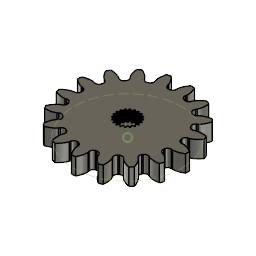
Main+assembly (Autodesk Fusion 360 archive; units mm, degrees)
design "Gear"
part number: 2025-12-15-16-50-46-728
description: Spur Gear; Module: 1.5; Num Teeth: 17; Pressure Angle: 20.0; Backlash: 0.15 mm
part number: 2025-12-15-16-51-44-285
Autodesk Fusion 360 part; units mm, degrees
(part 1 of 6)
sketch "Sketch1" plane through (0, 0, 0) normal (0, 0, 1) x (1, 0, 0) in component "Spur Gear (17 teeth)"
  circle A0 centre (0, 0) radius 10.8992
  circle A1 centre (0, 0) radius 0.5
extrude "Extrude1" add sketch "Sketch1" along normal blind 4 in component "Spur Gear (17 teeth)"
sketch "Sketch2" plane through (0, 0, 0) normal (0, 0, 1) x (1, 0, 0) in component "Spur Gear (17 teeth)"
  spline S0 degree 5 poles (11.9159, -1.2481) (11.9225, -1.2488) (11.9358, -1.25) (11.9557, -1.2512) (11.9823, -1.2518) (12.0157, -1.2511) (12.0491, -1.2494) (12.0825, -1.247) (12.116, -1.2443) (12.1495, -1.2413) (12.183, -1.238) (12.2166, -1.2344) (12.2501, -1.2304) (12.2837, -1.2259) (12.3173, -1.2209) (12.3509, -1.2154) (12.3845, -1.2095) (12.4181, -1.2032) (12.4517, -1.1966) (12.4853, -1.1898) (12.5189, -1.1827) (12.5525, -1.1752) (12.5861, -1.1675) (12.6197, -1.1594) (12.6533, -1.1511) (12.6869, -1.1424) (12.7205, -1.1334) (12.7541, -1.1241) (12.7876, -1.1146) (12.8212, -1.1048) (12.8547, -1.0948) (12.8882, -1.0845) (12.9218, -1.0739) (12.9553, -1.063) (12.9888, -1.0519) (13.0222, -1.0406) (13.0557, -1.029) (13.0891, -1.0171) (13.1225, -1.0051) (13.1559, -0.9927) (13.1893, -0.9802) (13.2227, -0.9674) (13.256, -0.9543) (13.2893, -0.9411) (13.3226, -0.9276) (13.3559, -0.9139) (13.3891, -0.8999) (13.4223, -0.8858) (13.4555, -0.8714) (13.4887, -0.8568) (13.5218, -0.842) (13.5549, -0.8269) (13.588, -0.8117) (13.6211, -0.7962) (13.6541, -0.7805) (13.6871, -0.7646) (13.72, -0.7485) (13.753, -0.7322) (13.7858, -0.7157) (13.8187, -0.699) (13.8515, -0.6821) (13.8843, -0.665) (13.9171, -0.6476) (13.9498, -0.6301) (13.9825, -0.6124) (14.0151, -0.5945) (14.0477, -0.5764) (14.0803, -0.558) (14.1128, -0.5395) (14.1453, -0.5209) (14.1777, -0.502) (14.2036, -0.4867) (14.223, -0.4752) (14.236, -0.4674) (14.2425, -0.4636) knots 0 0 0 0 0 0 0.01428571 0.02857143 0.04285714 0.05714286 0.07142857 0.08571429 0.1 0.11428571 0.12857143 0.14285714 0.15714286 0.17142857 0.18571429 0.2 0.21428571 0.22857143 0.24285714 0.25714286 0.27142857 0.28571429 0.3 0.31428571 0.32857143 0.34285714 0.35714286 0.37142857 0.38571429 0.4 0.41428571 0.42857143 0.44285714 0.45714286 0.47142857 0.48571429 0.5 0.51428571 0.52857143 0.54285714 0.55714286 0.57142857 0.58571429 0.6 0.61428571 0.62857143 0.64285714 0.65714286 0.67142857 0.68571429 0.7 0.71428571 0.72857143 0.74285714 0.75714286 0.77142857 0.78571429 0.8 0.81428571 0.82857143 0.84285714 0.85714286 0.87142857 0.88571429 0.9 0.91428571 0.92857143 0.94285714 0.95714286 0.97142857 0.98571429 1 1 1 1 1 1
  spline S1 degree 5 poles (11.9159, 1.2481) (11.9225, 1.2488) (11.9358, 1.25) (11.9557, 1.2512) (11.9823, 1.2518) (12.0157, 1.2511) (12.0491, 1.2494) (12.0825, 1.247) (12.116, 1.2443) (12.1495, 1.2413) (12.183, 1.238) (12.2166, 1.2344) (12.2501, 1.2304) (12.2837, 1.2259) (12.3173, 1.2209) (12.3509, 1.2154) (12.3845, 1.2095) (12.4181, 1.2032) (12.4517, 1.1966) (12.4853, 1.1898) (12.5189, 1.1827) (12.5525, 1.1752) (12.5861, 1.1675) (12.6197, 1.1594) (12.6533, 1.1511) (12.6869, 1.1424) (12.7205, 1.1334) (12.7541, 1.1241) (12.7876, 1.1146) (12.8212, 1.1048) (12.8547, 1.0948) (12.8882, 1.0845) (12.9218, 1.0739) (12.9553, 1.063) (12.9888, 1.0519) (13.0222, 1.0406) (13.0557, 1.029) (13.0891, 1.0171) (13.1225, 1.0051) (13.1559, 0.9927) (13.1893, 0.9802) (13.2227, 0.9674) (13.256, 0.9543) (13.2893, 0.9411) (13.3226, 0.9276) (13.3559, 0.9139) (13.3891, 0.8999) (13.4223, 0.8858) (13.4555, 0.8714) (13.4887, 0.8568) (13.5218, 0.842) (13.5549, 0.8269) (13.588, 0.8117) (13.6211, 0.7962) (13.6541, 0.7805) (13.6871, 0.7646) (13.72, 0.7485) (13.753, 0.7322) (13.7858, 0.7157) (13.8187, 0.699) (13.8515, 0.6821) (13.8843, 0.665) (13.9171, 0.6476) (13.9498, 0.6301) (13.9825, 0.6124) (14.0151, 0.5945) (14.0477, 0.5764) (14.0803, 0.558) (14.1128, 0.5395) (14.1453, 0.5209) (14.1777, 0.502) (14.2036, 0.4867) (14.223, 0.4752) (14.236, 0.4674) (14.2425, 0.4636) knots 0 0 0 0 0 0 0.01428571 0.02857143 0.04285714 0.05714286 0.07142857 0.08571429 0.1 0.11428571 0.12857143 0.14285714 0.15714286 0.17142857 0.18571429 0.2 0.21428571 0.22857143 0.24285714 0.25714286 0.27142857 0.28571429 0.3 0.31428571 0.32857143 0.34285714 0.35714286 0.37142857 0.38571429 0.4 0.41428571 0.42857143 0.44285714 0.45714286 0.47142857 0.48571429 0.5 0.51428571 0.52857143 0.54285714 0.55714286 0.57142857 0.58571429 0.6 0.61428571 0.62857143 0.64285714 0.65714286 0.67142857 0.68571429 0.7 0.71428571 0.72857143 0.74285714 0.75714286 0.77142857 0.78571429 0.8 0.81428571 0.82857143 0.84285714 0.85714286 0.87142857 0.88571429 0.9 0.91428571 0.92857143 0.94285714 0.95714286 0.97142857 0.98571429 1 1 1 1 1 1
  arc A0 (14.2425, -0.4636) -> (14.2425, 0.4636) centre (0, 0) ccw
  line L0 (10.83, -1.1354) -> (11.9159, -1.2481)
  line L1 (10.83, 1.1354) -> (11.9159, 1.2481)
  line L2 (10.83, -1.1354) -> (10.83, 1.1354)
  point P0 (12.0789, -1.2472)
  point P1 (12.2435, -1.2311)
  point P2 (12.4089, -1.2049)
  point P3 (12.575, -1.17)
  point P4 (12.7416, -1.1275)
  point P5 (12.9085, -1.078)
  point P6 (13.0757, -1.0219)
  point P7 (13.2429, -0.9594)
  point P8 (13.4101, -0.891)
  point P9 (13.5772, -0.8166)
  point P10 (13.7441, -0.7366)
  point P11 (13.9106, -0.651)
  point P12 (14.0768, -0.5599)
  point P13 (12.0789, 1.2472)
  point P14 (12.2435, 1.2311)
  point P15 (12.4089, 1.2049)
  point P16 (12.575, 1.17)
  point P17 (12.7416, 1.1275)
  point P18 (12.9085, 1.078)
  point P19 (13.0757, 1.0219)
  point P20 (13.2429, 0.9594)
  point P21 (13.4101, 0.891)
  point P22 (13.5772, 0.8166)
  point P23 (13.7441, 0.7366)
  point P24 (13.9106, 0.651)
  point P25 (14.0768, 0.5599)
extrude "Extrude2" add sketch "Sketch2" along normal blind 4 in component "Spur Gear (17 teeth)"
fillet "Fillet1" radius 0.8 2 edges at (10.8398, -1.1364, 2) (10.8398, 1.1364, 2) in component "Spur Gear (17 teeth)"
pattern_circular "C-Pattern1" count 17 over 360 about axis through (0, 0, 0) along (0, 0, 1) of "Extrude2", "Fillet1" in component "Spur Gear (17 teeth)"
sketch "Sketch3" plane through (0, 0, 0) normal (0, 0, 1) x (1, 0, 0) in component "Spur Gear (17 teeth)"
  circle A0 centre (0, 0) radius 12.75 construction
sketch "Sketch8" plane through (0, 0, 4) normal (0, 0, 1) x (-1, 0, 0)
  arc A0 (-10.6889, 2.1309) -> (-10.7368, 1.8743) centre (0, 0) ccw
  arc A1 (-11.6075, 1.2161) -> (-10.7368, 1.8743) centre (-11.5249, 2.0118) ccw
  line L0 (-11.6075, 1.2161) -> (-11.9159, 1.2481)
  spline S0 degree 5 poles (-11.9159, 1.2481) (-11.9225, 1.2488) (-11.9358, 1.25) (-11.9557, 1.2512) (-11.9823, 1.2518) (-12.0157, 1.2511) (-12.0491, 1.2494) (-12.0825, 1.247) (-12.116, 1.2443) (-12.1495, 1.2413) (-12.183, 1.238) (-12.2166, 1.2344) (-12.2501, 1.2304) (-12.2837, 1.2259) (-12.3173, 1.2209) (-12.3509, 1.2154) (-12.3845, 1.2095) (-12.4181, 1.2032) (-12.4517, 1.1966) (-12.4853, 1.1898) (-12.5189, 1.1827) (-12.5525, 1.1752) (-12.5861, 1.1675) (-12.6197, 1.1594) (-12.6533, 1.1511) (-12.6869, 1.1424) (-12.7205, 1.1334) (-12.7541, 1.1241) (-12.7876, 1.1146) (-12.8212, 1.1048) (-12.8547, 1.0948) (-12.8882, 1.0845) (-12.9218, 1.0739) (-12.9553, 1.063) (-12.9888, 1.0519) (-13.0222, 1.0406) (-13.0557, 1.029) (-13.0891, 1.0171) (-13.1225, 1.0051) (-13.1559, 0.9927) (-13.1893, 0.9802) (-13.2227, 0.9674) (-13.256, 0.9543) (-13.2893, 0.9411) (-13.3226, 0.9276) (-13.3559, 0.9139) (-13.3891, 0.8999) (-13.4223, 0.8858) (-13.4555, 0.8714) (-13.4887, 0.8568) (-13.5218, 0.842) (-13.5549, 0.8269) (-13.588, 0.8117) (-13.6211, 0.7962) (-13.6541, 0.7805) (-13.6871, 0.7646) (-13.72, 0.7485) (-13.753, 0.7322) (-13.7858, 0.7157) (-13.8187, 0.699) (-13.8515, 0.6821) (-13.8843, 0.665) (-13.9171, 0.6476) (-13.9498, 0.6301) (-13.9825, 0.6124) (-14.0151, 0.5945) (-14.0477, 0.5764) (-14.0803, 0.558) (-14.1128, 0.5395) (-14.1453, 0.5209) (-14.1777, 0.502) (-14.2036, 0.4867) (-14.223, 0.4752) (-14.236, 0.4674) (-14.2425, 0.4636) knots 0 0 0 0 0 0 0.01428571 0.02857143 0.04285714 0.05714286 0.07142857 0.08571429 0.1 0.11428571 0.12857143 0.14285714 0.15714286 0.17142857 0.18571429 0.2 0.21428571 0.22857143 0.24285714 0.25714286 0.27142857 0.28571429 0.3 0.31428571 0.32857143 0.34285714 0.35714286 0.37142857 0.38571429 0.4 0.41428571 0.42857143 0.44285714 0.45714286 0.47142857 0.48571429 0.5 0.51428571 0.52857143 0.54285714 0.55714286 0.57142857 0.58571429 0.6 0.61428571 0.62857143 0.64285714 0.65714286 0.67142857 0.68571429 0.7 0.71428571 0.72857143 0.74285714 0.75714286 0.77142857 0.78571429 0.8 0.81428571 0.82857143 0.84285714 0.85714286 0.87142857 0.88571429 0.9 0.91428571 0.92857143 0.94285714 0.95714286 0.97142857 0.98571429 1 1 1 1 1 1
  arc A2 (-14.2425, 0.4636) -> (-14.2425, -0.4636) centre (0, 0) ccw
  spline S1 degree 5 poles (-14.2425, -0.4636) (-14.236, -0.4674) (-14.223, -0.4752) (-14.2036, -0.4867) (-14.1777, -0.502) (-14.1453, -0.5209) (-14.1128, -0.5395) (-14.0803, -0.558) (-14.0477, -0.5764) (-14.0151, -0.5945) (-13.9825, -0.6124) (-13.9498, -0.6301) (-13.9171, -0.6476) (-13.8843, -0.665) (-13.8515, -0.6821) (-13.8187, -0.699) (-13.7858, -0.7157) (-13.753, -0.7322) (-13.72, -0.7485) (-13.6871, -0.7646) (-13.6541, -0.7805) (-13.6211, -0.7962) (-13.588, -0.8117) (-13.5549, -0.8269) (-13.5218, -0.842) (-13.4887, -0.8568) (-13.4555, -0.8714) (-13.4223, -0.8858) (-13.3891, -0.8999) (-13.3559, -0.9139) (-13.3226, -0.9276) (-13.2893, -0.9411) (-13.256, -0.9543) (-13.2227, -0.9674) (-13.1893, -0.9802) (-13.1559, -0.9927) (-13.1225, -1.0051) (-13.0891, -1.0171) (-13.0557, -1.029) (-13.0222, -1.0406) (-12.9888, -1.0519) (-12.9553, -1.063) (-12.9218, -1.0739) (-12.8882, -1.0845) (-12.8547, -1.0948) (-12.8212, -1.1048) (-12.7876, -1.1146) (-12.7541, -1.1241) (-12.7205, -1.1334) (-12.6869, -1.1424) (-12.6533, -1.1511) (-12.6197, -1.1594) (-12.5861, -1.1675) (-12.5525, -1.1752) (-12.5189, -1.1827) (-12.4853, -1.1898) (-12.4517, -1.1966) (-12.4181, -1.2032) (-12.3845, -1.2095) (-12.3509, -1.2154) (-12.3173, -1.2209) (-12.2837, -1.2259) (-12.2501, -1.2304) (-12.2166, -1.2344) (-12.183, -1.238) (-12.1495, -1.2413) (-12.116, -1.2443) (-12.0825, -1.247) (-12.0491, -1.2494) (-12.0157, -1.2511) (-11.9823, -1.2518) (-11.9557, -1.2512) (-11.9358, -1.25) (-11.9225, -1.2488) (-11.9159, -1.2481) knots -1 -1 -1 -1 -1 -1 -0.98571429 -0.97142857 -0.95714286 -0.94285714 -0.92857143 -0.91428571 -0.9 -0.88571429 -0.87142857 -0.85714286 -0.84285714 -0.82857143 -0.81428571 -0.8 -0.78571429 -0.77142857 -0.75714286 -0.74285714 -0.72857143 -0.71428571 -0.7 -0.68571429 -0.67142857 -0.65714286 -0.64285714 -0.62857143 -0.61428571 -0.6 -0.58571429 -0.57142857 -0.55714286 -0.54285714 -0.52857143 -0.51428571 -0.5 -0.48571429 -0.47142857 -0.45714286 -0.44285714 -0.42857143 -0.41428571 -0.4 -0.38571429 -0.37142857 -0.35714286 -0.34285714 -0.32857143 -0.31428571 -0.3 -0.28571429 -0.27142857 -0.25714286 -0.24285714 -0.22857143 -0.21428571 -0.2 -0.18571429 -0.17142857 -0.15714286 -0.14285714 -0.12857143 -0.11428571 -0.1 -0.08571429 -0.07142857 -0.05714286 -0.04285714 -0.02857143 -0.01428571 0 0 0 0 0 0
  line L1 (-11.9159, -1.2481) -> (-11.6075, -1.2161)
  arc A3 (-10.7368, -1.8743) -> (-11.6075, -1.2161) centre (-11.5249, -2.0118) ccw
  arc A4 (-10.7368, -1.8743) -> (-10.6889, -2.1309) centre (0, 0) ccw
  arc A5 (-11.263, -3.0591) -> (-10.6889, -2.1309) centre (-11.4734, -2.2873) ccw
  line L2 (-11.263, -3.0591) -> (-11.5621, -3.1407)
  spline S2 degree 5 poles (-11.5621, -3.1407) (-11.5685, -3.1424) (-11.5813, -3.1461) (-11.6004, -3.1522) (-11.6254, -3.1612) (-11.6563, -3.1739) (-11.6868, -3.1876) (-11.7171, -3.2019) (-11.7473, -3.2166) (-11.7775, -3.2315) (-11.8076, -3.2466) (-11.8376, -3.2621) (-11.8674, -3.2779) (-11.8971, -3.2943) (-11.9266, -3.3111) (-11.9559, -3.3283) (-11.9851, -3.346) (-12.0142, -3.364) (-12.0431, -3.3822) (-12.072, -3.4008) (-12.1008, -3.4195) (-12.1294, -3.4386) (-12.1579, -3.458) (-12.1864, -3.4776) (-12.2147, -3.4976) (-12.2429, -3.5178) (-12.2709, -3.5383) (-12.2989, -3.5591) (-12.3267, -3.5801) (-12.3545, -3.6013) (-12.3821, -3.6228) (-12.4097, -3.6446) (-12.4371, -3.6665) (-12.4644, -3.6887) (-12.4917, -3.7112) (-12.5188, -3.7338) (-12.5458, -3.7568) (-12.5727, -3.7799) (-12.5995, -3.8032) (-12.6262, -3.8268) (-12.6528, -3.8505) (-12.6792, -3.8745) (-12.7056, -3.8987) (-12.7319, -3.9231) (-12.7581, -3.9477) (-12.7841, -3.9725) (-12.8101, -3.9975) (-12.8359, -4.0228) (-12.8617, -4.0482) (-12.8873, -4.0738) (-12.9129, -4.0996) (-12.9383, -4.1255) (-12.9637, -4.1517) (-12.9889, -4.1781) (-13.014, -4.2046) (-13.039, -4.2314) (-13.0639, -4.2583) (-13.0888, -4.2854) (-13.1135, -4.3126) (-13.1381, -4.3401) (-13.1626, -4.3677) (-13.1869, -4.3955) (-13.2112, -4.4235) (-13.2354, -4.4517) (-13.2595, -4.48) (-13.2834, -4.5085) (-13.3073, -4.5372) (-13.331, -4.566) (-13.3547, -4.595) (-13.3782, -4.6242) (-13.4016, -4.6535) (-13.4203, -4.6771) (-13.4342, -4.6949) (-13.4435, -4.7068) (-13.4482, -4.7127) knots 0 0 0 0 0 0 0.01428571 0.02857143 0.04285714 0.05714286 0.07142857 0.08571429 0.1 0.11428571 0.12857143 0.14285714 0.15714286 0.17142857 0.18571429 0.2 0.21428571 0.22857143 0.24285714 0.25714286 0.27142857 0.28571429 0.3 0.31428571 0.32857143 0.34285714 0.35714286 0.37142857 0.38571429 0.4 0.41428571 0.42857143 0.44285714 0.45714286 0.47142857 0.48571429 0.5 0.51428571 0.52857143 0.54285714 0.55714286 0.57142857 0.58571429 0.6 0.61428571 0.62857143 0.64285714 0.65714286 0.67142857 0.68571429 0.7 0.71428571 0.72857143 0.74285714 0.75714286 0.77142857 0.78571429 0.8 0.81428571 0.82857143 0.84285714 0.85714286 0.87142857 0.88571429 0.9 0.91428571 0.92857143 0.94285714 0.95714286 0.97142857 0.98571429 1 1 1 1 1 1
  arc A6 (-13.4482, -4.7127) -> (-13.1132, -5.5772) centre (0, 0) ccw
  spline S3 degree 5 poles (-13.1132, -5.5772) (-13.1058, -5.5785) (-13.0909, -5.581) (-13.0687, -5.5848) (-13.039, -5.5896) (-13.0019, -5.5955) (-12.9649, -5.6012) (-12.9279, -5.6067) (-12.8909, -5.6121) (-12.8539, -5.6172) (-12.817, -5.6221) (-12.7802, -5.6268) (-12.7433, -5.6313) (-12.7065, -5.6356) (-12.6698, -5.6398) (-12.6331, -5.6437) (-12.5964, -5.6474) (-12.5597, -5.6509) (-12.5232, -5.6542) (-12.4866, -5.6573) (-12.4501, -5.6602) (-12.4137, -5.6629) (-12.3773, -5.6654) (-12.3409, -5.6677) (-12.3046, -5.6697) (-12.2683, -5.6716) (-12.2321, -5.6732) (-12.196, -5.6747) (-12.1599, -5.6759) (-12.1239, -5.6769) (-12.0879, -5.6776) (-12.052, -5.6782) (-12.0161, -5.6785) (-11.9803, -5.6786) (-11.9446, -5.6785) (-11.9089, -5.6782) (-11.8733, -5.6776) (-11.8378, -5.6768) (-11.8023, -5.6758) (-11.767, -5.6745) (-11.7316, -5.673) (-11.6964, -5.6712) (-11.6613, -5.6692) (-11.6262, -5.667) (-11.5912, -5.6645) (-11.5563, -5.6618) (-11.5215, -5.6588) (-11.4867, -5.6555) (-11.4521, -5.652) (-11.4175, -5.6483) (-11.383, -5.6442) (-11.3487, -5.6399) (-11.3144, -5.6353) (-11.2803, -5.6304) (-11.2463, -5.6252) (-11.2124, -5.6197) (-11.1786, -5.6139) (-11.1449, -5.6079) (-11.1113, -5.6016) (-11.0778, -5.595) (-11.0445, -5.5879) (-11.0114, -5.5805) (-10.9784, -5.5726) (-10.9457, -5.5642) (-10.9131, -5.5554) (-10.8807, -5.5464) (-10.8484, -5.537) (-10.8162, -5.5275) (-10.7841, -5.5177) (-10.7523, -5.5072) (-10.721, -5.4958) (-10.6964, -5.4856) (-10.6782, -5.4773) (-10.6663, -5.4714) (-10.6604, -5.4683) knots -1 -1 -1 -1 -1 -1 -0.98571429 -0.97142857 -0.95714286 -0.94285714 -0.92857143 -0.91428571 -0.9 -0.88571429 -0.87142857 -0.85714286 -0.84285714 -0.82857143 -0.81428571 -0.8 -0.78571429 -0.77142857 -0.75714286 -0.74285714 -0.72857143 -0.71428571 -0.7 -0.68571429 -0.67142857 -0.65714286 -0.64285714 -0.62857143 -0.61428571 -0.6 -0.58571429 -0.57142857 -0.55714286 -0.54285714 -0.52857143 -0.51428571 -0.5 -0.48571429 -0.47142857 -0.45714286 -0.44285714 -0.42857143 -0.41428571 -0.4 -0.38571429 -0.37142857 -0.35714286 -0.34285714 -0.32857143 -0.31428571 -0.3 -0.28571429 -0.27142857 -0.25714286 -0.24285714 -0.22857143 -0.21428571 -0.2 -0.18571429 -0.17142857 -0.15714286 -0.14285714 -0.12857143 -0.11428571 -0.1 -0.08571429 -0.07142857 -0.05714286 -0.04285714 -0.02857143 -0.01428571 0 0 0 0 0 0
  line L3 (-10.6604, -5.4683) -> (-10.3844, -5.3271)
  arc A7 (-9.3347, -5.6263) -> (-10.3844, -5.3271) centre (-10.0199, -6.0393) ccw
  arc A8 (-9.3347, -5.6263) -> (-9.1973, -5.8483) centre (0, 0) ccw
  arc A9 (-9.3973, -6.9212) -> (-9.1973, -5.8483) centre (-9.8724, -6.2775) ccw
  line L4 (-9.3973, -6.9212) -> (-9.6468, -7.1053)
  spline S4 degree 5 poles (-9.6468, -7.1053) (-9.6522, -7.1093) (-9.6628, -7.1173) (-9.6783, -7.1298) (-9.6984, -7.1473) (-9.7226, -7.1703) (-9.7461, -7.1941) (-9.7692, -7.2184) (-9.7921, -7.243) (-9.8148, -7.2678) (-9.8374, -7.2928) (-9.8598, -7.318) (-9.8819, -7.3436) (-9.9037, -7.3695) (-9.9251, -7.3959) (-9.9462, -7.4226) (-9.967, -7.4496) (-9.9877, -7.4768) (-10.0081, -7.5043) (-10.0283, -7.532) (-10.0483, -7.5599) (-10.0682, -7.5881) (-10.0878, -7.6164) (-10.1072, -7.645) (-10.1264, -7.6738) (-10.1453, -7.7029) (-10.1641, -7.7321) (-10.1827, -7.7616) (-10.2011, -7.7913) (-10.2193, -7.8211) (-10.2373, -7.8511) (-10.2551, -7.8813) (-10.2728, -7.9117) (-10.2902, -7.9423) (-10.3075, -7.9731) (-10.3246, -8.004) (-10.3415, -8.0351) (-10.3582, -8.0664) (-10.3748, -8.0979) (-10.3912, -8.1295) (-10.4074, -8.1612) (-10.4234, -8.1932) (-10.4393, -8.2252) (-10.4549, -8.2575) (-10.4705, -8.2899) (-10.4858, -8.3224) (-10.501, -8.3551) (-10.516, -8.388) (-10.5308, -8.421) (-10.5455, -8.4541) (-10.56, -8.4874) (-10.5743, -8.5208) (-10.5885, -8.5544) (-10.6025, -8.5881) (-10.6163, -8.6219) (-10.63, -8.6559) (-10.6435, -8.69) (-10.6569, -8.7242) (-10.67, -8.7586) (-10.6831, -8.793) (-10.6959, -8.8277) (-10.7086, -8.8624) (-10.7211, -8.8973) (-10.7335, -8.9322) (-10.7457, -8.9674) (-10.7578, -9.0026) (-10.7697, -9.0379) (-10.7814, -9.0734) (-10.793, -9.109) (-10.8044, -9.1447) (-10.8156, -9.1805) (-10.8245, -9.2092) (-10.8311, -9.2309) (-10.8354, -9.2453) (-10.8376, -9.2525) knots 0 0 0 0 0 0 0.01428571 0.02857143 0.04285714 0.05714286 0.07142857 0.08571429 0.1 0.11428571 0.12857143 0.14285714 0.15714286 0.17142857 0.18571429 0.2 0.21428571 0.22857143 0.24285714 0.25714286 0.27142857 0.28571429 0.3 0.31428571 0.32857143 0.34285714 0.35714286 0.37142857 0.38571429 0.4 0.41428571 0.42857143 0.44285714 0.45714286 0.47142857 0.48571429 0.5 0.51428571 0.52857143 0.54285714 0.55714286 0.57142857 0.58571429 0.6 0.61428571 0.62857143 0.64285714 0.65714286 0.67142857 0.68571429 0.7 0.71428571 0.72857143 0.74285714 0.75714286 0.77142857 0.78571429 0.8 0.81428571 0.82857143 0.84285714 0.85714286 0.87142857 0.88571429 0.9 0.91428571 0.92857143 0.94285714 0.95714286 0.97142857 0.98571429 1 1 1 1 1 1
  arc A10 (-10.8376, -9.2525) -> (-10.213, -9.9377) centre (0, 0) ccw
  spline S5 degree 5 poles (-10.213, -9.9377) (-10.2056, -9.9362) (-10.1908, -9.9332) (-10.1687, -9.9286) (-10.1393, -9.9224) (-10.1026, -9.9145) (-10.066, -9.9064) (-10.0295, -9.8982) (-9.9931, -9.8898) (-9.9568, -9.8812) (-9.9206, -9.8725) (-9.8845, -9.8636) (-9.8485, -9.8545) (-9.8127, -9.8452) (-9.7769, -9.8358) (-9.7412, -9.8262) (-9.7057, -9.8164) (-9.6703, -9.8064) (-9.635, -9.7963) (-9.5998, -9.786) (-9.5647, -9.7755) (-9.5297, -9.7648) (-9.4949, -9.754) (-9.4601, -9.743) (-9.4255, -9.7318) (-9.3911, -9.7204) (-9.3567, -9.7089) (-9.3225, -9.6972) (-9.2884, -9.6853) (-9.2544, -9.6732) (-9.2206, -9.6609) (-9.1869, -9.6484) (-9.1534, -9.6358) (-9.12, -9.623) (-9.0867, -9.6099) (-9.0536, -9.5967) (-9.0206, -9.5833) (-8.9877, -9.5698) (-8.955, -9.556) (-8.9225, -9.542) (-8.8901, -9.5279) (-8.8579, -9.5135) (-8.8258, -9.4989) (-8.7939, -9.4842) (-8.7622, -9.4692) (-8.7306, -9.454) (-8.6993, -9.4387) (-8.668, -9.4231) (-8.637, -9.4073) (-8.6061, -9.3913) (-8.5754, -9.3751) (-8.545, -9.3587) (-8.5147, -9.342) (-8.4847, -9.3251) (-8.4548, -9.3079) (-8.4252, -9.2906) (-8.3957, -9.273) (-8.3665, -9.2552) (-8.3374, -9.2372) (-8.3086, -9.2189) (-8.2801, -9.2003) (-8.2519, -9.1814) (-8.224, -9.1622) (-8.1965, -9.1425) (-8.1693, -9.1226) (-8.1424, -9.1024) (-8.1156, -9.082) (-8.089, -9.0615) (-8.0627, -9.0407) (-8.0368, -9.0195) (-8.0117, -8.9976) (-7.9924, -8.9792) (-7.9785, -8.9648) (-7.9695, -8.955) (-7.9651, -8.9501) knots -1 -1 -1 -1 -1 -1 -0.98571429 -0.97142857 -0.95714286 -0.94285714 -0.92857143 -0.91428571 -0.9 -0.88571429 -0.87142857 -0.85714286 -0.84285714 -0.82857143 -0.81428571 -0.8 -0.78571429 -0.77142857 -0.75714286 -0.74285714 -0.72857143 -0.71428571 -0.7 -0.68571429 -0.67142857 -0.65714286 -0.64285714 -0.62857143 -0.61428571 -0.6 -0.58571429 -0.57142857 -0.55714286 -0.54285714 -0.52857143 -0.51428571 -0.5 -0.48571429 -0.47142857 -0.45714286 -0.44285714 -0.42857143 -0.41428571 -0.4 -0.38571429 -0.37142857 -0.35714286 -0.34285714 -0.32857143 -0.31428571 -0.3 -0.28571429 -0.27142857 -0.25714286 -0.24285714 -0.22857143 -0.21428571 -0.2 -0.18571429 -0.17142857 -0.15714286 -0.14285714 -0.12857143 -0.11428571 -0.1 -0.08571429 -0.07142857 -0.05714286 -0.04285714 -0.02857143 -0.01428571 0 0 0 0 0 0
  line L5 (-7.9651, -8.9501) -> (-7.7588, -8.7186)
  arc A11 (-6.6719, -8.6185) -> (-7.7588, -8.7186) centre (-7.1617, -9.2511) ccw
  arc A12 (-6.6719, -8.6185) -> (-6.4636, -8.7758) centre (0, 0) ccw
  arc A13 (-6.2625, -9.8485) -> (-6.4636, -8.7758) centre (-6.938, -9.4199) ccw
  line L6 (-6.2625, -9.8485) -> (-6.4286, -10.1103)
  spline S6 degree 5 poles (-6.4286, -10.1103) (-6.4322, -10.116) (-6.4392, -10.1273) (-6.4492, -10.1446) (-6.4616, -10.1682) (-6.4758, -10.1983) (-6.4892, -10.229) (-6.5019, -10.26) (-6.5144, -10.2912) (-6.5266, -10.3225) (-6.5387, -10.354) (-6.5504, -10.3856) (-6.5618, -10.4174) (-6.5727, -10.4495) (-6.5832, -10.4818) (-6.5932, -10.5143) (-6.6029, -10.547) (-6.6123, -10.5799) (-6.6214, -10.6129) (-6.6302, -10.646) (-6.6388, -10.6793) (-6.6472, -10.7127) (-6.6552, -10.7462) (-6.663, -10.7799) (-6.6705, -10.8137) (-6.6777, -10.8476) (-6.6846, -10.8817) (-6.6913, -10.9159) (-6.6977, -10.9502) (-6.7039, -10.9846) (-6.7098, -11.0191) (-6.7155, -11.0537) (-6.721, -11.0884) (-6.7262, -11.1232) (-6.7312, -11.1582) (-6.736, -11.1932) (-6.7405, -11.2283) (-6.7448, -11.2635) (-6.7489, -11.2988) (-6.7528, -11.3342) (-6.7564, -11.3697) (-6.7598, -11.4053) (-6.763, -11.4409) (-6.766, -11.4766) (-6.7688, -11.5125) (-6.7713, -11.5483) (-6.7736, -11.5843) (-6.7758, -11.6204) (-6.7777, -11.6565) (-6.7794, -11.6927) (-6.7809, -11.729) (-6.7822, -11.7653) (-6.7833, -11.8017) (-6.7842, -11.8382) (-6.7848, -11.8747) (-6.7853, -11.9113) (-6.7856, -11.948) (-6.7857, -11.9848) (-6.7856, -12.0216) (-6.7852, -12.0584) (-6.7847, -12.0953) (-6.784, -12.1323) (-6.7831, -12.1694) (-6.782, -12.2065) (-6.7807, -12.2436) (-6.7792, -12.2808) (-6.7775, -12.3181) (-6.7757, -12.3554) (-6.7736, -12.3927) (-6.7713, -12.4302) (-6.7689, -12.4676) (-6.7668, -12.4976) (-6.7651, -12.5202) (-6.764, -12.5352) (-6.7634, -12.5427) knots 0 0 0 0 0 0 0.01428571 0.02857143 0.04285714 0.05714286 0.07142857 0.08571429 0.1 0.11428571 0.12857143 0.14285714 0.15714286 0.17142857 0.18571429 0.2 0.21428571 0.22857143 0.24285714 0.25714286 0.27142857 0.28571429 0.3 0.31428571 0.32857143 0.34285714 0.35714286 0.37142857 0.38571429 0.4 0.41428571 0.42857143 0.44285714 0.45714286 0.47142857 0.48571429 0.5 0.51428571 0.52857143 0.54285714 0.55714286 0.57142857 0.58571429 0.6 0.61428571 0.62857143 0.64285714 0.65714286 0.67142857 0.68571429 0.7 0.71428571 0.72857143 0.74285714 0.75714286 0.77142857 0.78571429 0.8 0.81428571 0.82857143 0.84285714 0.85714286 0.87142857 0.88571429 0.9 0.91428571 0.92857143 0.94285714 0.95714286 0.97142857 0.98571429 1 1 1 1 1 1
  arc A14 (-6.7634, -12.5427) -> (-5.9334, -12.956) centre (0, 0) ccw
  spline S7 degree 5 poles (-5.9334, -12.956) (-5.9271, -12.9519) (-5.9144, -12.9438) (-5.8954, -12.9315) (-5.8702, -12.9151) (-5.8388, -12.8945) (-5.8076, -12.8737) (-5.7766, -12.8529) (-5.7457, -12.8319) (-5.7149, -12.8108) (-5.6843, -12.7895) (-5.6539, -12.7682) (-5.6236, -12.7467) (-5.5935, -12.7251) (-5.5636, -12.7034) (-5.5338, -12.6816) (-5.5042, -12.6596) (-5.4748, -12.6375) (-5.4455, -12.6153) (-5.4164, -12.593) (-5.3875, -12.5705) (-5.3587, -12.548) (-5.3301, -12.5253) (-5.3017, -12.5025) (-5.2735, -12.4795) (-5.2455, -12.4565) (-5.2176, -12.4333) (-5.1899, -12.41) (-5.1625, -12.3866) (-5.1352, -12.3631) (-5.1081, -12.3394) (-5.0811, -12.3156) (-5.0544, -12.2917) (-5.0279, -12.2677) (-5.0016, -12.2435) (-4.9754, -12.2192) (-4.9495, -12.1948) (-4.9238, -12.1703) (-4.8983, -12.1456) (-4.873, -12.1208) (-4.8479, -12.0959) (-4.8231, -12.0709) (-4.7984, -12.0458) (-4.774, -12.0205) (-4.7498, -11.995) (-4.7259, -11.9695) (-4.7022, -11.9438) (-4.6787, -11.918) (-4.6554, -11.8921) (-4.6324, -11.866) (-4.6097, -11.8398) (-4.5872, -11.8135) (-4.565, -11.787) (-4.5431, -11.7604) (-4.5215, -11.7336) (-4.5001, -11.7067) (-4.479, -11.6797) (-4.4582, -11.6525) (-4.4376, -11.6252) (-4.4173, -11.5978) (-4.3974, -11.5702) (-4.3779, -11.5424) (-4.3589, -11.5143) (-4.3404, -11.4861) (-4.3222, -11.4576) (-4.3044, -11.4291) (-4.2868, -11.4004) (-4.2694, -11.3717) (-4.2523, -11.3428) (-4.2359, -11.3137) (-4.2204, -11.2841) (-4.2091, -11.26) (-4.2013, -11.2416) (-4.1964, -11.2292) (-4.1941, -11.223) knots -1 -1 -1 -1 -1 -1 -0.98571429 -0.97142857 -0.95714286 -0.94285714 -0.92857143 -0.91428571 -0.9 -0.88571429 -0.87142857 -0.85714286 -0.84285714 -0.82857143 -0.81428571 -0.8 -0.78571429 -0.77142857 -0.75714286 -0.74285714 -0.72857143 -0.71428571 -0.7 -0.68571429 -0.67142857 -0.65714286 -0.64285714 -0.62857143 -0.61428571 -0.6 -0.58571429 -0.57142857 -0.55714286 -0.54285714 -0.52857143 -0.51428571 -0.5 -0.48571429 -0.47142857 -0.45714286 -0.44285714 -0.42857143 -0.41428571 -0.4 -0.38571429 -0.37142857 -0.35714286 -0.34285714 -0.32857143 -0.31428571 -0.3 -0.28571429 -0.27142857 -0.25714286 -0.24285714 -0.22857143 -0.21428571 -0.2 -0.18571429 -0.17142857 -0.15714286 -0.14285714 -0.12857143 -0.11428571 -0.1 -0.08571429 -0.07142857 -0.05714286 -0.04285714 -0.02857143 -0.01428571 0 0 0 0 0 0
  line L7 (-4.1941, -11.223) -> (-4.0853, -10.9327)
  arc A15 (-3.108, -10.4467) -> (-4.0853, -10.9327) centre (-3.3362, -11.2134) ccw
  arc A16 (-3.108, -10.4467) -> (-2.8569, -10.5181) centre (0, 0) ccw
  arc A17 (-2.2819, -11.4458) -> (-2.8569, -10.5181) centre (-3.0666, -11.2901) ccw
  line L8 (-2.2819, -11.4458) -> (-2.3422, -11.7499)
  spline S8 degree 5 poles (-2.3422, -11.7499) (-2.3435, -11.7564) (-2.346, -11.7695) (-2.349, -11.7893) (-2.3521, -11.8157) (-2.3545, -11.849) (-2.3558, -11.8824) (-2.3565, -11.9159) (-2.3569, -11.9495) (-2.357, -11.9832) (-2.3568, -12.0168) (-2.3564, -12.0506) (-2.3555, -12.0843) (-2.3541, -12.1182) (-2.3522, -12.1521) (-2.3498, -12.186) (-2.347, -12.22) (-2.3439, -12.2541) (-2.3404, -12.2882) (-2.3367, -12.3223) (-2.3327, -12.3564) (-2.3284, -12.3905) (-2.3238, -12.4247) (-2.3189, -12.4589) (-2.3137, -12.4931) (-2.3081, -12.5274) (-2.3023, -12.5616) (-2.2961, -12.5959) (-2.2897, -12.6302) (-2.2831, -12.6645) (-2.2762, -12.6989) (-2.269, -12.7332) (-2.2616, -12.7676) (-2.2539, -12.8019) (-2.2459, -12.8363) (-2.2377, -12.8707) (-2.2292, -12.905) (-2.2205, -12.9394) (-2.2116, -12.9738) (-2.2024, -13.0082) (-2.1929, -13.0426) (-2.1833, -13.077) (-2.1734, -13.1114) (-2.1633, -13.1458) (-2.1529, -13.1802) (-2.1423, -13.2146) (-2.1315, -13.249) (-2.1204, -13.2834) (-2.1092, -13.3177) (-2.0977, -13.3521) (-2.086, -13.3865) (-2.0741, -13.4208) (-2.0619, -13.4552) (-2.0496, -13.4895) (-2.037, -13.5238) (-2.0242, -13.5581) (-2.0113, -13.5924) (-1.9981, -13.6267) (-1.9847, -13.661) (-1.971, -13.6953) (-1.9572, -13.7295) (-1.9432, -13.7637) (-1.929, -13.7979) (-1.9145, -13.8321) (-1.8999, -13.8663) (-1.8851, -13.9005) (-1.8701, -13.9346) (-1.8548, -13.9687) (-1.8394, -14.0028) (-1.8238, -14.0369) (-1.808, -14.0709) (-1.7952, -14.0981) (-1.7855, -14.1185) (-1.779, -14.1321) (-1.7757, -14.1389) knots 0 0 0 0 0 0 0.01428571 0.02857143 0.04285714 0.05714286 0.07142857 0.08571429 0.1 0.11428571 0.12857143 0.14285714 0.15714286 0.17142857 0.18571429 0.2 0.21428571 0.22857143 0.24285714 0.25714286 0.27142857 0.28571429 0.3 0.31428571 0.32857143 0.34285714 0.35714286 0.37142857 0.38571429 0.4 0.41428571 0.42857143 0.44285714 0.45714286 0.47142857 0.48571429 0.5 0.51428571 0.52857143 0.54285714 0.55714286 0.57142857 0.58571429 0.6 0.61428571 0.62857143 0.64285714 0.65714286 0.67142857 0.68571429 0.7 0.71428571 0.72857143 0.74285714 0.75714286 0.77142857 0.78571429 0.8 0.81428571 0.82857143 0.84285714 0.85714286 0.87142857 0.88571429 0.9 0.91428571 0.92857143 0.94285714 0.95714286 0.97142857 0.98571429 1 1 1 1 1 1
  arc A18 (-1.7757, -14.1389) -> (-0.8525, -14.2245) centre (0, 0) ccw
  spline S9 degree 5 poles (-0.8525, -14.2245) (-0.8481, -14.2184) (-0.8392, -14.2062) (-0.8259, -14.1879) (-0.8083, -14.1635) (-0.7865, -14.133) (-0.7649, -14.1024) (-0.7435, -14.0717) (-0.7223, -14.041) (-0.7012, -14.0102) (-0.6804, -13.9793) (-0.6597, -13.9484) (-0.6392, -13.9175) (-0.619, -13.8864) (-0.5989, -13.8554) (-0.579, -13.8242) (-0.5593, -13.7931) (-0.5399, -13.7619) (-0.5206, -13.7306) (-0.5015, -13.6992) (-0.4827, -13.6679) (-0.464, -13.6364) (-0.4455, -13.605) (-0.4273, -13.5734) (-0.4093, -13.5418) (-0.3915, -13.5102) (-0.3739, -13.4785) (-0.3565, -13.4468) (-0.3393, -13.415) (-0.3223, -13.3832) (-0.3056, -13.3514) (-0.2891, -13.3195) (-0.2728, -13.2875) (-0.2568, -13.2555) (-0.241, -13.2235) (-0.2254, -13.1914) (-0.21, -13.1593) (-0.1949, -13.1271) (-0.18, -13.0949) (-0.1654, -13.0627) (-0.151, -13.0304) (-0.1369, -12.9981) (-0.123, -12.9657) (-0.1094, -12.9333) (-0.096, -12.9009) (-0.0829, -12.8684) (-0.07, -12.8359) (-0.0575, -12.8034) (-0.0451, -12.7708) (-0.0331, -12.7382) (-0.0213, -12.7055) (-0.0099, -12.6729) (0.0012, -12.6401) (0.012, -12.6074) (0.0225, -12.5746) (0.0327, -12.5418) (0.0426, -12.509) (0.0523, -12.4761) (0.0616, -12.4432) (0.0706, -12.4103) (0.0792, -12.3774) (0.0873, -12.3444) (0.0949, -12.3114) (0.102, -12.2784) (0.1086, -12.2453) (0.115, -12.2122) (0.121, -12.1791) (0.1269, -12.1461) (0.1323, -12.113) (0.1371, -12.0799) (0.1409, -12.0467) (0.1428, -12.0202) (0.1434, -12.0002) (0.1434, -11.9869) (0.1433, -11.9802) knots -1 -1 -1 -1 -1 -1 -0.98571429 -0.97142857 -0.95714286 -0.94285714 -0.92857143 -0.91428571 -0.9 -0.88571429 -0.87142857 -0.85714286 -0.84285714 -0.82857143 -0.81428571 -0.8 -0.78571429 -0.77142857 -0.75714286 -0.74285714 -0.72857143 -0.71428571 -0.7 -0.68571429 -0.67142857 -0.65714286 -0.64285714 -0.62857143 -0.61428571 -0.6 -0.58571429 -0.57142857 -0.55714286 -0.54285714 -0.52857143 -0.51428571 -0.5 -0.48571429 -0.47142857 -0.45714286 -0.44285714 -0.42857143 -0.41428571 -0.4 -0.38571429 -0.37142857 -0.35714286 -0.34285714 -0.32857143 -0.31428571 -0.3 -0.28571429 -0.27142857 -0.25714286 -0.24285714 -0.22857143 -0.21428571 -0.2 -0.18571429 -0.17142857 -0.15714286 -0.14285714 -0.12857143 -0.11428571 -0.1 -0.08571429 -0.07142857 -0.05714286 -0.04285714 -0.02857143 -0.01428571 0 0 0 0 0 0
  line L9 (0.1433, -11.9802) -> (0.1399, -11.6702)
  arc A19 (0.8756, -10.864) -> (0.1399, -11.6702) centre (0.9399, -11.6614) ccw
  arc A20 (0.8756, -10.864) -> (1.1356, -10.8399) centre (0, 0) ccw
  arc A21 (2.0069, -11.4972) -> (1.1356, -10.8399) centre (1.2189, -11.6355) ccw
  line L10 (2.0069, -11.4972) -> (2.0605, -11.8026)
  spline S10 degree 5 poles (2.0605, -11.8026) (2.0616, -11.8091) (2.0641, -11.8222) (2.0684, -11.8417) (2.0751, -11.8675) (2.0849, -11.8994) (2.0957, -11.931) (2.1071, -11.9626) (2.1189, -11.994) (2.131, -12.0254) (2.1433, -12.0568) (2.1559, -12.088) (2.169, -12.1192) (2.1825, -12.1503) (2.1965, -12.1812) (2.211, -12.212) (2.2259, -12.2427) (2.2411, -12.2733) (2.2566, -12.3038) (2.2724, -12.3343) (2.2884, -12.3647) (2.3048, -12.3949) (2.3214, -12.4251) (2.3384, -12.4553) (2.3556, -12.4853) (2.3732, -12.5152) (2.391, -12.5451) (2.4091, -12.5748) (2.4274, -12.6045) (2.446, -12.6341) (2.4649, -12.6636) (2.484, -12.693) (2.5033, -12.7224) (2.5229, -12.7516) (2.5428, -12.7808) (2.5628, -12.8099) (2.5831, -12.8389) (2.6037, -12.8678) (2.6245, -12.8966) (2.6455, -12.9254) (2.6667, -12.9541) (2.6881, -12.9826) (2.7098, -13.0111) (2.7316, -13.0396) (2.7537, -13.0679) (2.776, -13.0961) (2.7985, -13.1243) (2.8212, -13.1524) (2.8442, -13.1803) (2.8673, -13.2082) (2.8906, -13.2361) (2.9141, -13.2638) (2.9379, -13.2914) (2.9618, -13.319) (2.9859, -13.3465) (3.0102, -13.3738) (3.0347, -13.4011) (3.0594, -13.4283) (3.0843, -13.4554) (3.1094, -13.4825) (3.1346, -13.5094) (3.1601, -13.5363) (3.1857, -13.563) (3.2115, -13.5897) (3.2375, -13.6163) (3.2636, -13.6428) (3.29, -13.6692) (3.3165, -13.6955) (3.3432, -13.7217) (3.3701, -13.7478) (3.3971, -13.7738) (3.4189, -13.7946) (3.4353, -13.8101) (3.4463, -13.8205) (3.4518, -13.8256) knots 0 0 0 0 0 0 0.01428571 0.02857143 0.04285714 0.05714286 0.07142857 0.08571429 0.1 0.11428571 0.12857143 0.14285714 0.15714286 0.17142857 0.18571429 0.2 0.21428571 0.22857143 0.24285714 0.25714286 0.27142857 0.28571429 0.3 0.31428571 0.32857143 0.34285714 0.35714286 0.37142857 0.38571429 0.4 0.41428571 0.42857143 0.44285714 0.45714286 0.47142857 0.48571429 0.5 0.51428571 0.52857143 0.54285714 0.55714286 0.57142857 0.58571429 0.6 0.61428571 0.62857143 0.64285714 0.65714286 0.67142857 0.68571429 0.7 0.71428571 0.72857143 0.74285714 0.75714286 0.77142857 0.78571429 0.8 0.81428571 0.82857143 0.84285714 0.85714286 0.87142857 0.88571429 0.9 0.91428571 0.92857143 0.94285714 0.95714286 0.97142857 0.98571429 1 1 1 1 1 1
  arc A22 (3.4518, -13.8256) -> (4.3435, -13.5719) centre (0, 0) ccw
  spline S11 degree 5 poles (4.3435, -13.5719) (4.3455, -13.5646) (4.3493, -13.5501) (4.3551, -13.5282) (4.3627, -13.4991) (4.372, -13.4627) (4.3811, -13.4264) (4.39, -13.39) (4.3987, -13.3537) (4.4072, -13.3174) (4.4155, -13.2811) (4.4236, -13.2448) (4.4315, -13.2086) (4.4392, -13.1723) (4.4467, -13.1361) (4.454, -13.0999) (4.4611, -13.0637) (4.4679, -13.0276) (4.4746, -12.9914) (4.4811, -12.9553) (4.4873, -12.9193) (4.4934, -12.8832) (4.4992, -12.8472) (4.5048, -12.8112) (4.5102, -12.7752) (4.5154, -12.7393) (4.5204, -12.7034) (4.5252, -12.6676) (4.5297, -12.6317) (4.534, -12.5959) (4.5381, -12.5602) (4.542, -12.5245) (4.5456, -12.4888) (4.549, -12.4532) (4.5522, -12.4176) (4.5551, -12.382) (4.5578, -12.3465) (4.5603, -12.3111) (4.5626, -12.2757) (4.5646, -12.2403) (4.5663, -12.205) (4.5678, -12.1698) (4.5691, -12.1346) (4.5701, -12.0995) (4.5708, -12.0644) (4.5713, -12.0294) (4.5716, -11.9944) (4.5715, -11.9595) (4.5713, -11.9247) (4.5707, -11.89) (4.5699, -11.8553) (4.5687, -11.8207) (4.5673, -11.7861) (4.5655, -11.7517) (4.5635, -11.7173) (4.5611, -11.6831) (4.5585, -11.6489) (4.5556, -11.6148) (4.5525, -11.5807) (4.549, -11.5468) (4.5451, -11.513) (4.5407, -11.4793) (4.5359, -11.4458) (4.5305, -11.4124) (4.5248, -11.3792) (4.5188, -11.346) (4.5125, -11.313) (4.5059, -11.28) (4.4991, -11.2472) (4.4916, -11.2146) (4.4832, -11.1823) (4.4753, -11.1569) (4.4687, -11.1381) (4.4639, -11.1256) (4.4614, -11.1194) knots -1 -1 -1 -1 -1 -1 -0.98571429 -0.97142857 -0.95714286 -0.94285714 -0.92857143 -0.91428571 -0.9 -0.88571429 -0.87142857 -0.85714286 -0.84285714 -0.82857143 -0.81428571 -0.8 -0.78571429 -0.77142857 -0.75714286 -0.74285714 -0.72857143 -0.71428571 -0.7 -0.68571429 -0.67142857 -0.65714286 -0.64285714 -0.62857143 -0.61428571 -0.6 -0.58571429 -0.57142857 -0.55714286 -0.54285714 -0.52857143 -0.51428571 -0.5 -0.48571429 -0.47142857 -0.45714286 -0.44285714 -0.42857143 -0.41428571 -0.4 -0.38571429 -0.37142857 -0.35714286 -0.34285714 -0.32857143 -0.31428571 -0.3 -0.28571429 -0.27142857 -0.25714286 -0.24285714 -0.22857143 -0.21428571 -0.2 -0.18571429 -0.17142857 -0.15714286 -0.14285714 -0.12857143 -0.11428571 -0.1 -0.08571429 -0.07142857 -0.05714286 -0.04285714 -0.02857143 -0.01428571 0 0 0 0 0 0
  line L11 (4.4614, -11.1194) -> (4.3462, -10.8316)
  arc A23 (4.741, -9.8141) -> (4.3462, -10.8316) centre (5.089, -10.5344) ccw
  arc A24 (4.741, -9.8141) -> (4.9747, -9.6977) centre (0, 0) ccw
  arc A25 (6.0246, -9.9959) -> (4.9747, -9.6977) centre (5.3398, -10.4095) ccw
  line L12 (6.0246, -9.9959) -> (6.1849, -10.2612)
  spline S12 degree 5 poles (6.1849, -10.2612) (6.1884, -10.2669) (6.1954, -10.2783) (6.2064, -10.2949) (6.222, -10.3165) (6.2426, -10.3427) (6.2642, -10.3683) (6.2862, -10.3936) (6.3086, -10.4186) (6.3312, -10.4436) (6.354, -10.4683) (6.377, -10.493) (6.4005, -10.5173) (6.4243, -10.5414) (6.4485, -10.5651) (6.4732, -10.5886) (6.4981, -10.6119) (6.5234, -10.6349) (6.5489, -10.6578) (6.5746, -10.6805) (6.6005, -10.703) (6.6267, -10.7254) (6.6531, -10.7475) (6.6798, -10.7695) (6.7067, -10.7912) (6.7339, -10.8128) (6.7613, -10.8342) (6.789, -10.8554) (6.8168, -10.8764) (6.8448, -10.8973) (6.8731, -10.918) (6.9015, -10.9386) (6.9301, -10.9589) (6.959, -10.9791) (6.988, -10.9992) (7.0172, -11.0191) (7.0467, -11.0388) (7.0763, -11.0583) (7.106, -11.0777) (7.136, -11.0969) (7.1661, -11.116) (7.1965, -11.1349) (7.2269, -11.1537) (7.2576, -11.1722) (7.2884, -11.1907) (7.3194, -11.209) (7.3506, -11.2271) (7.3819, -11.2451) (7.4134, -11.2629) (7.445, -11.2805) (7.4768, -11.298) (7.5088, -11.3154) (7.5409, -11.3326) (7.5732, -11.3497) (7.6056, -11.3666) (7.6381, -11.3833) (7.6708, -11.3999) (7.7037, -11.4164) (7.7367, -11.4327) (7.7698, -11.4488) (7.8031, -11.4648) (7.8365, -11.4806) (7.8701, -11.4963) (7.9038, -11.5119) (7.9376, -11.5273) (7.9716, -11.5425) (8.0057, -11.5576) (8.0399, -11.5726) (8.0743, -11.5874) (8.1088, -11.602) (8.1434, -11.6166) (8.1712, -11.628) (8.1921, -11.6366) (8.2061, -11.6423) (8.2131, -11.6451) knots 0 0 0 0 0 0 0.01428571 0.02857143 0.04285714 0.05714286 0.07142857 0.08571429 0.1 0.11428571 0.12857143 0.14285714 0.15714286 0.17142857 0.18571429 0.2 0.21428571 0.22857143 0.24285714 0.25714286 0.27142857 0.28571429 0.3 0.31428571 0.32857143 0.34285714 0.35714286 0.37142857 0.38571429 0.4 0.41428571 0.42857143 0.44285714 0.45714286 0.47142857 0.48571429 0.5 0.51428571 0.52857143 0.54285714 0.55714286 0.57142857 0.58571429 0.6 0.61428571 0.62857143 0.64285714 0.65714286 0.67142857 0.68571429 0.7 0.71428571 0.72857143 0.74285714 0.75714286 0.77142857 0.78571429 0.8 0.81428571 0.82857143 0.84285714 0.85714286 0.87142857 0.88571429 0.9 0.91428571 0.92857143 0.94285714 0.95714286 0.97142857 0.98571429 1 1 1 1 1 1
  arc A26 (8.2131, -11.6451) -> (8.9529, -11.0864) centre (0, 0) ccw
  spline S13 degree 5 poles (8.9529, -11.0864) (8.9521, -11.0789) (8.9505, -11.0639) (8.948, -11.0414) (8.9446, -11.0116) (8.9401, -10.9743) (8.9354, -10.9371) (8.9306, -10.9) (8.9256, -10.863) (8.9204, -10.826) (8.915, -10.7892) (8.9095, -10.7524) (8.9037, -10.7158) (8.8978, -10.6792) (8.8917, -10.6427) (8.8854, -10.6063) (8.879, -10.57) (8.8723, -10.5338) (8.8655, -10.4977) (8.8585, -10.4617) (8.8513, -10.4258) (8.8439, -10.39) (8.8363, -10.3543) (8.8286, -10.3188) (8.8206, -10.2833) (8.8125, -10.2479) (8.8042, -10.2126) (8.7956, -10.1775) (8.7869, -10.1424) (8.778, -10.1075) (8.7689, -10.0727) (8.7596, -10.038) (8.7501, -10.0034) (8.7404, -9.9689) (8.7305, -9.9346) (8.7204, -9.9004) (8.7102, -9.8663) (8.6997, -9.8324) (8.689, -9.7986) (8.6781, -9.7649) (8.6669, -9.7313) (8.6556, -9.6979) (8.6441, -9.6646) (8.6323, -9.6315) (8.6203, -9.5985) (8.6081, -9.5657) (8.5957, -9.533) (8.5831, -9.5005) (8.5703, -9.4681) (8.5572, -9.4359) (8.5439, -9.4039) (8.5303, -9.372) (8.5165, -9.3404) (8.5024, -9.3089) (8.4881, -9.2776) (8.4735, -9.2465) (8.4588, -9.2155) (8.4437, -9.1848) (8.4285, -9.1542) (8.413, -9.1238) (8.3971, -9.0937) (8.3809, -9.0638) (8.3643, -9.0343) (8.3472, -9.0051) (8.3299, -8.9762) (8.3123, -8.9475) (8.2945, -8.919) (8.2765, -8.8906) (8.2582, -8.8624) (8.2395, -8.8347) (8.2199, -8.8077) (8.2034, -8.7868) (8.1904, -8.7717) (8.1815, -8.7618) (8.1769, -8.7569) knots -1 -1 -1 -1 -1 -1 -0.98571429 -0.97142857 -0.95714286 -0.94285714 -0.92857143 -0.91428571 -0.9 -0.88571429 -0.87142857 -0.85714286 -0.84285714 -0.82857143 -0.81428571 -0.8 -0.78571429 -0.77142857 -0.75714286 -0.74285714 -0.72857143 -0.71428571 -0.7 -0.68571429 -0.67142857 -0.65714286 -0.64285714 -0.62857143 -0.61428571 -0.6 -0.58571429 -0.57142857 -0.55714286 -0.54285714 -0.52857143 -0.51428571 -0.5 -0.48571429 -0.47142857 -0.45714286 -0.44285714 -0.42857143 -0.41428571 -0.4 -0.38571429 -0.37142857 -0.35714286 -0.34285714 -0.32857143 -0.31428571 -0.3 -0.28571429 -0.27142857 -0.25714286 -0.24285714 -0.22857143 -0.21428571 -0.2 -0.18571429 -0.17142857 -0.15714286 -0.14285714 -0.12857143 -0.11428571 -0.1 -0.08571429 -0.07142857 -0.05714286 -0.04285714 -0.02857143 -0.01428571 0 0 0 0 0 0
  line L13 (8.1769, -8.7569) -> (7.9656, -8.5301)
  arc A27 (7.9661, -7.4387) -> (7.9656, -8.5301) centre (8.5508, -7.9847) ccw
  arc A28 (7.9661, -7.4387) -> (8.142, -7.2457) centre (0, 0) ccw
  arc A29 (9.2287, -7.1445) -> (8.142, -7.2457) centre (8.7396, -7.7776) ccw
  line L14 (9.2287, -7.1445) -> (9.474, -7.3341)
  spline S14 degree 5 poles (9.474, -7.3341) (9.4793, -7.3382) (9.49, -7.3461) (9.5063, -7.3577) (9.5286, -7.3722) (9.5573, -7.3892) (9.5866, -7.4053) (9.6163, -7.4209) (9.6462, -7.4362) (9.6763, -7.4512) (9.7065, -7.4661) (9.7369, -7.4807) (9.7675, -7.495) (9.7985, -7.5088) (9.8297, -7.5222) (9.8611, -7.5352) (9.8928, -7.5479) (9.9247, -7.5603) (9.9567, -7.5724) (9.9889, -7.5842) (10.0212, -7.5959) (10.0537, -7.6073) (10.0863, -7.6184) (10.1191, -7.6292) (10.1521, -7.6398) (10.1852, -7.6501) (10.2185, -7.6601) (10.2519, -7.6699) (10.2855, -7.6795) (10.3192, -7.6888) (10.353, -7.6979) (10.3869, -7.7068) (10.421, -7.7155) (10.4552, -7.7239) (10.4895, -7.7321) (10.5239, -7.74) (10.5585, -7.7478) (10.5931, -7.7553) (10.6279, -7.7626) (10.6628, -7.7697) (10.6978, -7.7766) (10.7329, -7.7833) (10.7681, -7.7898) (10.8034, -7.7961) (10.8388, -7.8021) (10.8743, -7.808) (10.9099, -7.8136) (10.9456, -7.8191) (10.9814, -7.8243) (11.0173, -7.8293) (11.0533, -7.8342) (11.0893, -7.8388) (11.1255, -7.8433) (11.1617, -7.8475) (11.1981, -7.8516) (11.2345, -7.8554) (11.271, -7.8591) (11.3075, -7.8625) (11.3442, -7.8658) (11.3809, -7.8689) (11.4177, -7.8718) (11.4546, -7.8745) (11.4916, -7.877) (11.5286, -7.8793) (11.5657, -7.8815) (11.6029, -7.8834) (11.6402, -7.8852) (11.6775, -7.8868) (11.7149, -7.8882) (11.7524, -7.8894) (11.7899, -7.8904) (11.82, -7.891) (11.8425, -7.8915) (11.8576, -7.8917) (11.8651, -7.8918) knots 0 0 0 0 0 0 0.01428571 0.02857143 0.04285714 0.05714286 0.07142857 0.08571429 0.1 0.11428571 0.12857143 0.14285714 0.15714286 0.17142857 0.18571429 0.2 0.21428571 0.22857143 0.24285714 0.25714286 0.27142857 0.28571429 0.3 0.31428571 0.32857143 0.34285714 0.35714286 0.37142857 0.38571429 0.4 0.41428571 0.42857143 0.44285714 0.45714286 0.47142857 0.48571429 0.5 0.51428571 0.52857143 0.54285714 0.55714286 0.57142857 0.58571429 0.6 0.61428571 0.62857143 0.64285714 0.65714286 0.67142857 0.68571429 0.7 0.71428571 0.72857143 0.74285714 0.75714286 0.77142857 0.78571429 0.8 0.81428571 0.82857143 0.84285714 0.85714286 0.87142857 0.88571429 0.9 0.91428571 0.92857143 0.94285714 0.95714286 0.97142857 0.98571429 1 1 1 1 1 1
  arc A30 (11.8651, -7.8918) -> (12.3532, -7.1036) centre (0, 0) ccw
  spline S15 degree 5 poles (12.3532, -7.1036) (12.3498, -7.0969) (12.3428, -7.0835) (12.3324, -7.0634) (12.3184, -7.0368) (12.3007, -7.0037) (12.283, -6.9707) (12.2651, -6.9378) (12.247, -6.9051) (12.2288, -6.8726) (12.2105, -6.8402) (12.1921, -6.8079) (12.1735, -6.7758) (12.1547, -6.7438) (12.1359, -6.712) (12.1169, -6.6803) (12.0977, -6.6488) (12.0785, -6.6175) (12.0591, -6.5863) (12.0395, -6.5552) (12.0198, -6.5243) (12, -6.4936) (11.9801, -6.4631) (11.96, -6.4327) (11.9397, -6.4025) (11.9194, -6.3724) (11.8989, -6.3426) (11.8782, -6.3129) (11.8574, -6.2833) (11.8365, -6.254) (11.8154, -6.2248) (11.7942, -6.1958) (11.7729, -6.167) (11.7514, -6.1384) (11.7298, -6.1099) (11.708, -6.0817) (11.6861, -6.0536) (11.6641, -6.0257) (11.6419, -5.9981) (11.6195, -5.9706) (11.597, -5.9433) (11.5744, -5.9163) (11.5516, -5.8894) (11.5287, -5.8628) (11.5056, -5.8363) (11.4824, -5.8101) (11.459, -5.7842) (11.4355, -5.7584) (11.4118, -5.7328) (11.388, -5.7075) (11.364, -5.6824) (11.3399, -5.6576) (11.3155, -5.6331) (11.291, -5.6088) (11.2664, -5.5848) (11.2416, -5.5611) (11.2166, -5.5376) (11.1915, -5.5143) (11.1662, -5.4913) (11.1407, -5.4686) (11.1151, -5.4462) (11.0892, -5.4242) (11.063, -5.4027) (11.0366, -5.3817) (11.01, -5.361) (10.9832, -5.3406) (10.9563, -5.3204) (10.9292, -5.3004) (10.9021, -5.2808) (10.8746, -5.2617) (10.8466, -5.2436) (10.8236, -5.2301) (10.806, -5.2206) (10.7941, -5.2146) (10.7881, -5.2117) knots -1 -1 -1 -1 -1 -1 -0.98571429 -0.97142857 -0.95714286 -0.94285714 -0.92857143 -0.91428571 -0.9 -0.88571429 -0.87142857 -0.85714286 -0.84285714 -0.82857143 -0.81428571 -0.8 -0.78571429 -0.77142857 -0.75714286 -0.74285714 -0.72857143 -0.71428571 -0.7 -0.68571429 -0.67142857 -0.65714286 -0.64285714 -0.62857143 -0.61428571 -0.6 -0.58571429 -0.57142857 -0.55714286 -0.54285714 -0.52857143 -0.51428571 -0.5 -0.48571429 -0.47142857 -0.45714286 -0.44285714 -0.42857143 -0.41428571 -0.4 -0.38571429 -0.37142857 -0.35714286 -0.34285714 -0.32857143 -0.31428571 -0.3 -0.28571429 -0.27142857 -0.25714286 -0.24285714 -0.22857143 -0.21428571 -0.2 -0.18571429 -0.17142857 -0.15714286 -0.14285714 -0.12857143 -0.11428571 -0.1 -0.08571429 -0.07142857 -0.05714286 -0.04285714 -0.02857143 -0.01428571 0 0 0 0 0 0
  line L15 (10.7881, -5.2117) -> (10.5091, -5.0766)
  arc A31 (10.1153, -4.0587) -> (10.5091, -5.0766) centre (10.8578, -4.3566) ccw
  arc A32 (10.1153, -4.0587) -> (10.2096, -3.8152) centre (0, 0) ccw
  arc A33 (11.1864, -3.3283) -> (10.2096, -3.8152) centre (10.959, -4.0953) ccw
  line L16 (11.1864, -3.3283) -> (11.4837, -3.4164)
  spline S16 degree 5 poles (11.4837, -3.4164) (11.4901, -3.4183) (11.5029, -3.4219) (11.5222, -3.4268) (11.5483, -3.4323) (11.5812, -3.4377) (11.6144, -3.4421) (11.6477, -3.4459) (11.6811, -3.4494) (11.7146, -3.4526) (11.7481, -3.4556) (11.7817, -3.4582) (11.8155, -3.4604) (11.8493, -3.4622) (11.8832, -3.4634) (11.9173, -3.4641) (11.9514, -3.4645) (11.9855, -3.4645) (12.0198, -3.4643) (12.0541, -3.4637) (12.0884, -3.4629) (12.1228, -3.4618) (12.1573, -3.4603) (12.1918, -3.4586) (12.2263, -3.4565) (12.261, -3.4541) (12.2956, -3.4515) (12.3303, -3.4485) (12.3651, -3.4454) (12.3999, -3.4419) (12.4347, -3.4382) (12.4695, -3.4342) (12.5044, -3.43) (12.5393, -3.4255) (12.5743, -3.4207) (12.6093, -3.4157) (12.6443, -3.4104) (12.6794, -3.4049) (12.7144, -3.3992) (12.7495, -3.3932) (12.7846, -3.387) (12.8198, -3.3806) (12.8549, -3.3739) (12.8901, -3.367) (12.9253, -3.3598) (12.9606, -3.3525) (12.9958, -3.3449) (13.031, -3.337) (13.0663, -3.329) (13.1016, -3.3207) (13.1369, -3.3122) (13.1722, -3.3035) (13.2075, -3.2946) (13.2428, -3.2855) (13.2782, -3.2762) (13.3135, -3.2666) (13.3489, -3.2568) (13.3842, -3.2469) (13.4196, -3.2367) (13.455, -3.2263) (13.4903, -3.2157) (13.5257, -3.2049) (13.5611, -3.1939) (13.5965, -3.1826) (13.6319, -3.1712) (13.6672, -3.1596) (13.7026, -3.1478) (13.738, -3.1358) (13.7733, -3.1236) (13.8087, -3.1112) (13.8441, -3.0986) (13.8724, -3.0883) (13.8936, -3.0806) (13.9077, -3.0753) (13.9148, -3.0727) knots 0 0 0 0 0 0 0.01428571 0.02857143 0.04285714 0.05714286 0.07142857 0.08571429 0.1 0.11428571 0.12857143 0.14285714 0.15714286 0.17142857 0.18571429 0.2 0.21428571 0.22857143 0.24285714 0.25714286 0.27142857 0.28571429 0.3 0.31428571 0.32857143 0.34285714 0.35714286 0.37142857 0.38571429 0.4 0.41428571 0.42857143 0.44285714 0.45714286 0.47142857 0.48571429 0.5 0.51428571 0.52857143 0.54285714 0.55714286 0.57142857 0.58571429 0.6 0.61428571 0.62857143 0.64285714 0.65714286 0.67142857 0.68571429 0.7 0.71428571 0.72857143 0.74285714 0.75714286 0.77142857 0.78571429 0.8 0.81428571 0.82857143 0.84285714 0.85714286 0.87142857 0.88571429 0.9 0.91428571 0.92857143 0.94285714 0.95714286 0.97142857 0.98571429 1 1 1 1 1 1
  arc A34 (13.9148, -3.0727) -> (14.0851, -2.1614) centre (0, 0) ccw